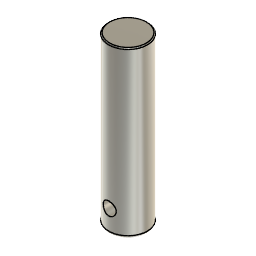
hammer (Autodesk Fusion 360 design; units mm, degrees)
part number: 2025-10-12-17-45-08-986
Autodesk Fusion 360 part; units mm, degrees
sketch "handle" plane through (0, 0, 0) normal (0, 1, 0) x (1, 0, 0)
  line L0 (0, -14.3854) -> (0, -177.8)
  line L1 (0, -177.8) -> (0, -127.8)
  line L2 (0, -177.8) -> (19.05, -177.8)
  line L3 (19.05, -177.8) -> (19.05, -14.3854)
  line L4 (19.05, -14.3854) -> (0, -14.3854)
  dimension "d2" = 177.8
  constraint parallel L0 L1
  constraint perpendicular L1 L2
  constraint perpendicular L3 L4
  measures "d2" distance of origin L0.end
revolve "Revolve1" add sketch "handle" angle 360 about axis through (0, 0, 14.3854) along (0, 0, 1)
fillet "Fillet1" radius 3 1 edges at (-17.7608, -6.8888, 14.3854) 1 faces at (-7.2281, 0.9464, 14.3854)
sketch "hole" plane through (0, 0, 0) normal (0, 1, 0) x (1, 0, 0)
  line L0 (0, 0) -> (0, -32.4031)
  circle A0 centre (0, -32.4031) radius 6.35
  dimension "d10" = 12.7
  constraint coincident L0.start origin
  constraint vertical L0
  constraint coincident L0.end A0.centre
  measures "d10" diameter of A0
hole "Hole2" at (0, -19.05, 32.7368) direction (0, 1, 0) diameter 12.7 end through all
move_face "MoveFace1" to x (1, 0, 0) y (0, 1, 0) z (0, 0, 1) at (0, 0, 15) 1 faces at (8.4885, 17.0543, 76.1675)
move_face "MoveFace2" to x (0.939693, 0, 0.34202) y (0, 1, 0) z (-0.34202, 0, 0.939693) at (11.3236, 0, 11.9735) 1 faces at (1.7932, 6.3315, 26.6452)
move_face "MoveFace3" to x (0.965926, 0, -0.258819) y (0, 1, 0) z (0.258819, 0, 0.965926) at (-11.1135, 0, -3.5106) 1 faces at (-4.0829, 6.1688, 37.982)
fillet "Fillet6" radius 1 1 edges at (-17.7608, -6.8888, 177.8)
move_face "OffsetFaces1" offset -1 1 faces at (-8.3651, -1.4992, 14.3854)
named bodies: "handle"
